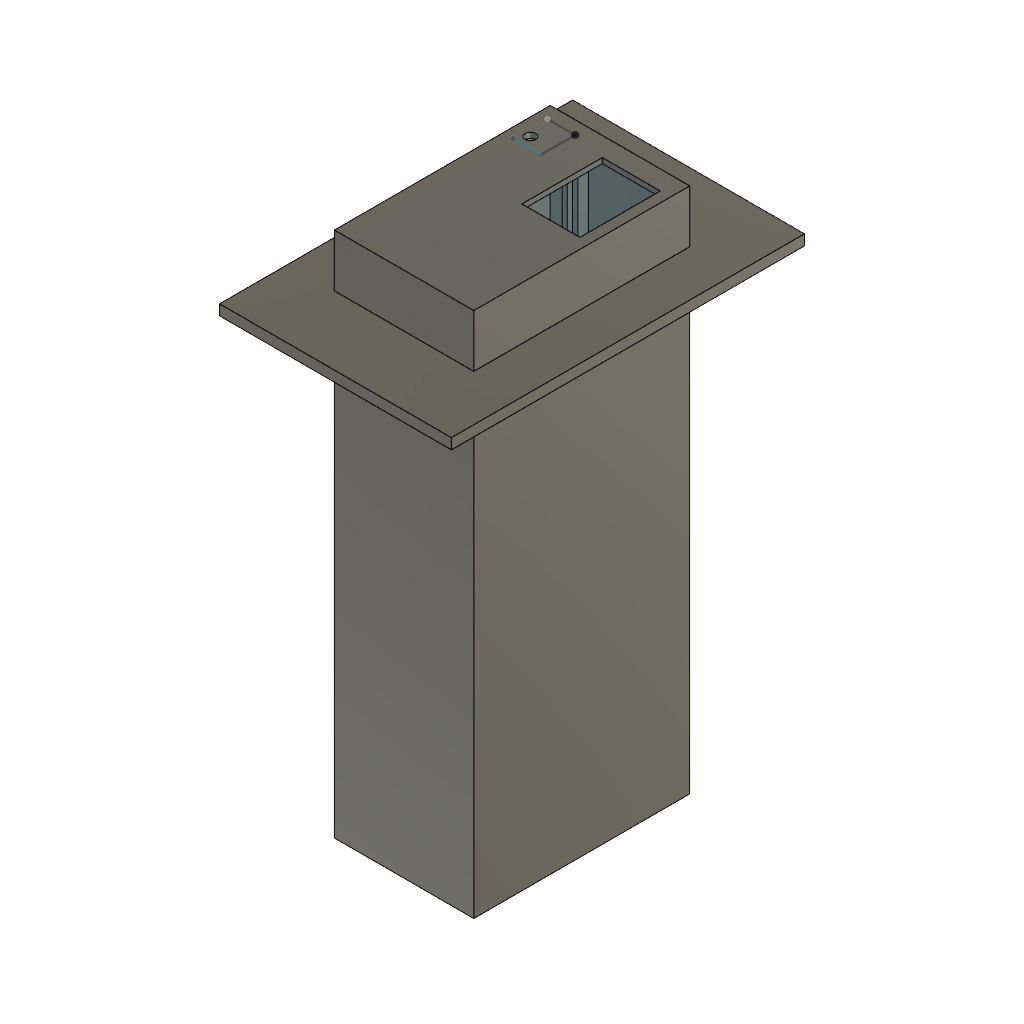
CASE_CONVEYOR (Autodesk Fusion 360 design; units mm, degrees)
part number: 2026-11-19-20-31-42-839
Autodesk Fusion 360 part; units mm, degrees
sketch "Sketch1" plane through (0, 0, 0) normal (0, 0, 1) x (1, 0, 0)
  line L0 (26.5, 41) -> (-26.5, 41)
  line L1 (-26.5, 41) -> (-26.5, -41)
  line L2 (-26.5, -41) -> (26.5, -41)
  line L3 (26.5, -41) -> (26.5, 41)
  line L4 (26.5, 41) -> (-26.5, -41) construction
  line L5 (-26.5, 41) -> (26.5, -41) construction
  dimension "d1" = 53
  dimension "d2" = 82
  constraint horizontal L0
  constraint perpendicular L0 L1
  constraint parallel L0 L2
  constraint parallel L1 L3
  constraint coincident L4 origin
  constraint coincident L5 origin
  measures "d1" distance of L1.end L2.end
  measures "d2" distance of L0.end L1.end
sketch "Sketch2" plane through (0, 0, 0) normal (0, 0, 1) x (1, 0, 0)
  line L0 (22.568, 3.2137) -> (0.568, 3.2137)
  line L1 (0.568, 3.2137) -> (0.568, 33.7137)
  line L2 (0.568, 33.7137) -> (22.568, 33.7137)
  line L3 (22.568, 33.7137) -> (22.568, 3.2137)
  line L4 (22.568, 3.2137) -> (0.568, 33.7137) construction
  line L5 (0.568, 3.2137) -> (22.568, 33.7137) construction
  point P0 (11.568, 18.4637)
  dimension "d3" = 22
  dimension "d4" = 30.5
  constraint horizontal L0
  constraint perpendicular L0 L1
  constraint parallel L0 L2
  constraint parallel L1 L3
  constraint coincident L4 P0
  constraint coincident L5 P0
  measures "d3" distance of L1.end L2.end
  measures "d4" distance of L0.end L1.end
extrude "Extrude1" add sketch "Sketch1" along normal blind 200 makes body 1
extrude "Extrude2" cut sketch "Sketch2" along normal blind 200 bodies 1
sketch "Sketch3" plane through (0, 0, 0) normal (0, 0, 1) x (1, 0, 0)
  line L0 (24.5, -39) -> (-24.5, -39)
  line L1 (-24.5, -39) -> (-24.5, 39)
  line L2 (-24.5, 39) -> (24.5, 39)
  line L3 (24.5, 39) -> (24.5, -39)
  line L4 (24.5, -39) -> (-24.5, 39) construction
  line L5 (-24.5, -39) -> (24.5, 39) construction
  dimension "d9" = 49
  dimension "d10" = 78
  constraint horizontal L0
  constraint perpendicular L0 L1
  constraint parallel L0 L2
  constraint parallel L1 L3
  constraint coincident L4 origin
  constraint coincident L5 origin
  measures "d9" distance of L1.end L2.end
  measures "d10" distance of L0.end L1.end
extrude "Extrude3" cut sketch "Sketch3" along normal blind 198 bodies 1
sketch "Sketch7" plane through (0, 0, 198) normal (0, 0, -1) x (1, 0, 0)
  line L0 (22.568, -3.2137) -> (22.568, -33.7137)
  line L1 (22.568, -33.7137) -> (0.568, -33.7137)
  line L2 (0.568, -33.7137) -> (0.568, -3.2137)
  line L3 (0.568, -3.2137) -> (22.568, -3.2137)
  line L4 (-24.5, -39) -> (24.5, -39)
  line L5 (24.5, -39) -> (24.5, 39)
  line L6 (24.5, 39) -> (-24.5, 39)
  line L7 (-24.5, 39) -> (-24.5, -39)
  line L8 (-10, 39) -> (-15.8621, 39)
  line L9 (-15.8621, 35.0096) -> (-14, 35.0096)
  line L10 (-14, 35.0096) -> (-14, 38)
  line L11 (-14, 38) -> (-12, 38)
  line L12 (-12, 38) -> (-12, 35.0096)
  line L13 (-12, 35.0096) -> (-10, 35.0096)
  line L14 (-10, 35.0096) -> (-10, 39)
  line L15 (-10, -35) -> (-12, -35)
  line L16 (-12, -35) -> (-12, -38)
  line L17 (-12, -38) -> (-14, -38)
  line L18 (-14, -38) -> (-14, -35)
  line L19 (-14, -35) -> (-15.9, -35)
  line L20 (-15.9, -35) -> (-15.9, -39)
  line L21 (-10, -39) -> (-10, -35)
  line L22 (-10, -39) -> (-15.9, -39)
  line L23 (-15.8621, 39) -> (-15.8621, 35.0096)
  constraint coincident L6 L8.start
  constraint coincident L6 L8.end
  constraint parallel L6 L9
  constraint perpendicular L9 L10
  constraint perpendicular L10 L11
  constraint perpendicular L11 L12
  constraint perpendicular L10 L13
  constraint perpendicular L6 L14
  constraint horizontal L15
  constraint perpendicular L15 L16
  constraint perpendicular L16 L17
  constraint perpendicular L17 L18
  constraint perpendicular L18 L19
  constraint coincident L4 L20.end
  constraint perpendicular L4 L20
  constraint coincident L4 L21.start
  constraint perpendicular L15 L21
  constraint perpendicular L9 L23
extrude "Extrude5" add sketch "Sketch7" along normal blind 140 contours L4 L15 L16 L17 L18 L19 L20 L21 L22 | L6 L8 L9 L10 L11 L12 L13 L14 L23 bodies 1
sketch "Sketch8" plane through (0, 0, 198) normal (0, 0, -1) x (1, 0, 0)
  line L0 (22.568, -3.2137) -> (22.568, -33.7137)
  line L1 (22.568, -33.7137) -> (0.568, -33.7137)
  line L2 (0.568, -33.7137) -> (0.568, -3.2137)
  line L3 (0.568, -3.2137) -> (22.568, -3.2137)
  line L4 (-10, 39) -> (-10, 35.0096)
  line L5 (-10, 35.0096) -> (-12, 35.0096)
  line L6 (-12, 35.0096) -> (-12, 38)
  line L7 (-12, 38) -> (-14, 38)
  line L8 (-14, 38) -> (-14, 35.0096)
  line L9 (-14, 35.0096) -> (-15.8621, 35.0096)
  line L10 (-15.8621, 35.0096) -> (-15.8621, 39)
  line L11 (-15.8621, 39) -> (-24.5, 39)
  line L12 (-24.5, 39) -> (-24.5, -39)
  line L13 (-24.5, -39) -> (-15.9, -39)
  line L14 (-15.9, -39) -> (-15.9, -35)
  line L15 (-15.9, -35) -> (-14, -35)
  line L16 (-14, -35) -> (-14, -38)
  line L17 (-14, -38) -> (-12, -38)
  line L18 (-12, -38) -> (-12, -35)
  line L19 (-12, -35) -> (-10, -35)
  line L20 (-10, -35) -> (-10, -39)
  line L21 (-10, -39) -> (24.5, -39)
  line L22 (24.5, -39) -> (24.5, 39)
  line L23 (24.5, 39) -> (-10, 39)
  line L24 (-14, -38) -> (-14, -25)
  line L25 (-14, -25) -> (-24.5, -25)
  line L26 (-14, -38) -> (-24.5, -38)
  constraint coincident L16.end L17.start
  constraint perpendicular L15 L24
  constraint coincident L12 L25.end
  constraint perpendicular L12 L25
  constraint perpendicular L14 L26
sketch "Sketch9" plane through (0, 0, 198) normal (0, 0, -1) x (1, 0, 0)
  circle A0 centre (-20, -27) radius 2
  line L0 (-14, -38) -> (-24.5, -38)
  line L1 (-14, -38) -> (-14, -25)
  dimension "d19" = 4
  dimension "d20" = 11
  dimension "d21" = 6
  measures "d19" diameter of A0
  measures "d20" distance of A0.centre L0
  measures "d21" distance of A0.centre L1
extrude "Extrude6" cut sketch "Sketch9" against normal blind 2 bodies 1
sketch "Sketch10" plane through (0, 0, 198) normal (0, 0, -1) x (1, 0, 0)
  line L0 (19.5, 39) -> (19.5, 35)
  line L1 (19.5, 35) -> (17.5, 35)
  line L2 (17.5, 37) -> (15.5, 37)
  line L3 (15.5, 37) -> (15.5, 35)
  line L4 (17.5, 35) -> (17.5, 37)
  line L5 (15.5, 35) -> (13.5, 35)
  line L6 (13.5, 35) -> (13.5, 39)
  line L7 (13.5, 39) -> (19.5, 39)
  line L8 (24.5, -39) -> (24.5, 39)
  dimension "d24" = 5
  constraint vertical L0
  constraint perpendicular L0 L1
  constraint perpendicular L0 L2
  constraint perpendicular L2 L3
  constraint perpendicular L2 L4
  constraint perpendicular L3 L5
  constraint perpendicular L5 L6
  constraint perpendicular L0 L7
  measures "d24" distance of L0 L8
sketch "Sketch11" plane through (0, 0, 198) normal (0, 0, -1) x (1, 0, 0)
  line L0 (13.5, -34.5) -> (13.5, -31.5)
  line L1 (13.5, -31.5) -> (15.5, -31.5)
  line L2 (15.5, -31.5) -> (15.5, -33.5)
  line L3 (15.5, -33.5) -> (17.5, -33.5)
  line L4 (17.5, -33.5) -> (17.5, -31.5)
  line L5 (17.5, -31.5) -> (19.5, -31.5)
  line L6 (19.5, -31.5) -> (19.5, -33.5)
  line L7 (19.5, -33.5) -> (19.5, -38.9744)
  line L8 (19.5, -38.9744) -> (13.5, -38.9744)
  line L9 (13.5, -38.9744) -> (13.5, -34.5)
  line L10 (24.5, -39) -> (24.5, 39)
  line L11 (17.5, 37) -> (15.5, 37)
  dimension "d25" = 5
  dimension "d26" = 70.5
  dimension "d27" = 6
  constraint vertical L0
  constraint perpendicular L0 L1
  constraint perpendicular L1 L2
  constraint perpendicular L0 L3
  constraint perpendicular L3 L4
  constraint perpendicular L4 L5
  constraint perpendicular L5 L6
  constraint perpendicular L5 L7
  constraint perpendicular L7 L8
  measures "d25" distance of L6.end L10
  measures "d26" distance of L3 L11
  measures "d27" distance of L7.end L8.end
extrude "Extrude7" add sketch "Sketch11" along normal blind 140 and the other way blind -80 separate body makes body 2
extrude "Extrude8" add sketch "Sketch10" along normal blind 140 and the other way blind -20 bodies 1
sketch "Sketch12" plane through (0, 0, 200) normal (0, 0, 1) x (-1, 0, 0)
  line L0 (-26.5, 41) -> (-26.5, -41)
  line L1 (-26.5, -41) -> (26.5, -41)
  line L2 (26.5, -41) -> (26.5, 41)
  line L3 (26.5, 41) -> (-26.5, 41)
  line L4 (-44.05, -67.0632) -> (44.05, -67.0632)
  line L5 (44.05, -67.0632) -> (44.05, 67.0632)
  line L6 (44.05, 67.0632) -> (-44.05, 67.0632)
  line L7 (-44.05, 67.0632) -> (-44.05, -67.0632)
  line L8 (-44.05, -67.0632) -> (44.05, 67.0632) construction
  line L9 (44.05, -67.0632) -> (-44.05, 67.0632) construction
  line L10 (-22.568, -33.7137) -> (-22.568, -3.2137)
  line L11 (-22.568, -3.2137) -> (-0.568, -3.2137)
  line L12 (-0.568, -3.2137) -> (-0.568, -33.7137)
  line L13 (-0.568, -33.7137) -> (-22.568, -33.7137)
  circle A0 centre (20, -27) radius 2
  constraint horizontal L4
  constraint perpendicular L4 L5
  constraint parallel L4 L6
  constraint parallel L5 L7
  constraint coincident L8 origin
  constraint coincident L9 origin
extrude "Extrude9" add sketch "Sketch12" along normal blind -24 and the other way blind 20 contours L4 L5 L6 L7 bodies 1
